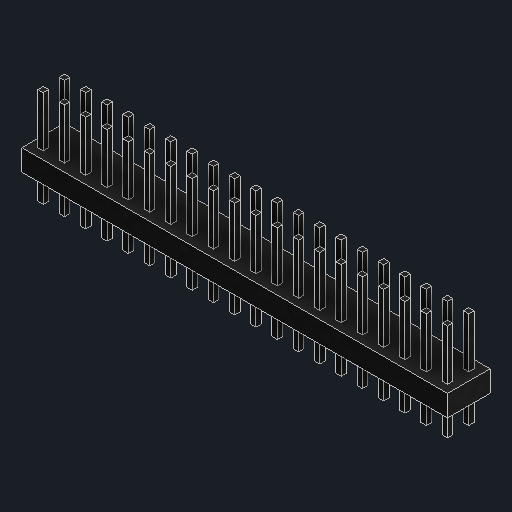
# Autodesk Inventor part: pi_header_2x20
Saved by Autodesk Inventor 2027.1 (Build 311270010, 270A)
## iProperties
Created: 2026-10-29
Part Number: pi_header_2x20
Material: Generic
Document SubType Name: Modeling
Designer: alexg
Density: 1 g/cm^3
Appearance: Black
Author: alexg
Autodesk Inventor part; units mm, degrees
ref_plane "YZ Plane" through (0, 0, 0) normal (1, 0, 0) x (0, 1, 0)
ref_plane "XY Plane" through (0, 0, 0) normal (0, 0, 1) x (1, 0, 0)
sketch "Plastic sketch" plane through (0, 0, 0) normal (0, 1, 0) x (-1, 0, 0)
  line L0 (25.4, -2.54) -> (-25.4, -2.54)
  line L1 (-25.4, -2.54) -> (-25.4, 2.54)
  line L2 (-25.4, 2.54) -> (25.4, 2.54)
  line L3 (25.4, 2.54) -> (25.4, -2.54)
  constraints: 8 end point, 2 parallel, 1 horizontal, 1 perpendicular
extrude "Plastic" add sketch "Plastic sketch" along normal blind 2.54
ref_plane "Work Plane1" through (0, -3, 0) normal (0, 1, 0) x (-1, 0, 0)
sketch "Pins sketch" plane through (0, -3, 0) normal (0, 1, 0) x (-1, 0, 0)
  line L0 (24.45, -1.59) -> (23.81, -1.59)
  line L1 (23.81, -1.59) -> (23.81, -0.95)
  line L2 (23.81, -0.95) -> (24.45, -0.95)
  line L3 (24.45, -0.95) -> (24.45, -1.59)
  line L4 (24.45, 0.95) -> (23.81, 0.95)
  line L5 (23.81, 0.95) -> (23.81, 1.59)
  line L6 (23.81, 1.59) -> (24.45, 1.59)
  line L7 (24.45, 1.59) -> (24.45, 0.95)
  line L8 (21.91, -1.59) -> (21.27, -1.59)
  line L9 (21.27, -1.59) -> (21.27, -0.95)
  line L10 (21.27, -0.95) -> (21.91, -0.95)
  line L11 (21.91, -0.95) -> (21.91, -1.59)
  line L12 (21.91, 0.95) -> (21.27, 0.95)
  line L13 (21.27, 0.95) -> (21.27, 1.59)
  line L14 (21.27, 1.59) -> (21.91, 1.59)
  line L15 (21.91, 1.59) -> (21.91, 0.95)
  line L16 (19.37, -1.59) -> (18.73, -1.59)
  line L17 (18.73, -1.59) -> (18.73, -0.95)
  line L18 (18.73, -0.95) -> (19.37, -0.95)
  line L19 (19.37, -0.95) -> (19.37, -1.59)
  line L20 (19.37, 0.95) -> (18.73, 0.95)
  line L21 (18.73, 0.95) -> (18.73, 1.59)
  line L22 (18.73, 1.59) -> (19.37, 1.59)
  line L23 (19.37, 1.59) -> (19.37, 0.95)
  line L24 (16.83, -1.59) -> (16.19, -1.59)
  line L25 (16.19, -1.59) -> (16.19, -0.95)
  line L26 (16.19, -0.95) -> (16.83, -0.95)
  line L27 (16.83, -0.95) -> (16.83, -1.59)
  line L28 (16.83, 0.95) -> (16.19, 0.95)
  line L29 (16.19, 0.95) -> (16.19, 1.59)
  line L30 (16.19, 1.59) -> (16.83, 1.59)
  line L31 (16.83, 1.59) -> (16.83, 0.95)
  line L32 (14.29, -1.59) -> (13.65, -1.59)
  line L33 (13.65, -1.59) -> (13.65, -0.95)
  line L34 (13.65, -0.95) -> (14.29, -0.95)
  line L35 (14.29, -0.95) -> (14.29, -1.59)
  line L36 (14.29, 0.95) -> (13.65, 0.95)
  line L37 (13.65, 0.95) -> (13.65, 1.59)
  line L38 (13.65, 1.59) -> (14.29, 1.59)
  line L39 (14.29, 1.59) -> (14.29, 0.95)
  line L40 (11.75, -1.59) -> (11.11, -1.59)
  line L41 (11.11, -1.59) -> (11.11, -0.95)
  line L42 (11.11, -0.95) -> (11.75, -0.95)
  line L43 (11.75, -0.95) -> (11.75, -1.59)
  line L44 (11.75, 0.95) -> (11.11, 0.95)
  line L45 (11.11, 0.95) -> (11.11, 1.59)
  line L46 (11.11, 1.59) -> (11.75, 1.59)
  line L47 (11.75, 1.59) -> (11.75, 0.95)
  line L48 (9.21, -1.59) -> (8.57, -1.59)
  line L49 (8.57, -1.59) -> (8.57, -0.95)
  line L50 (8.57, -0.95) -> (9.21, -0.95)
  line L51 (9.21, -0.95) -> (9.21, -1.59)
  line L52 (9.21, 0.95) -> (8.57, 0.95)
  line L53 (8.57, 0.95) -> (8.57, 1.59)
  line L54 (8.57, 1.59) -> (9.21, 1.59)
  line L55 (9.21, 1.59) -> (9.21, 0.95)
  line L56 (6.67, -1.59) -> (6.03, -1.59)
  line L57 (6.03, -1.59) -> (6.03, -0.95)
  line L58 (6.03, -0.95) -> (6.67, -0.95)
  line L59 (6.67, -0.95) -> (6.67, -1.59)
  line L60 (6.67, 0.95) -> (6.03, 0.95)
  line L61 (6.03, 0.95) -> (6.03, 1.59)
  line L62 (6.03, 1.59) -> (6.67, 1.59)
  line L63 (6.67, 1.59) -> (6.67, 0.95)
  line L64 (4.13, -1.59) -> (3.49, -1.59)
  line L65 (3.49, -1.59) -> (3.49, -0.95)
  line L66 (3.49, -0.95) -> (4.13, -0.95)
  line L67 (4.13, -0.95) -> (4.13, -1.59)
  line L68 (4.13, 0.95) -> (3.49, 0.95)
  line L69 (3.49, 0.95) -> (3.49, 1.59)
  line L70 (3.49, 1.59) -> (4.13, 1.59)
  line L71 (4.13, 1.59) -> (4.13, 0.95)
  line L72 (1.59, -1.59) -> (0.95, -1.59)
  line L73 (0.95, -1.59) -> (0.95, -0.95)
  line L74 (0.95, -0.95) -> (1.59, -0.95)
  line L75 (1.59, -0.95) -> (1.59, -1.59)
  line L76 (1.59, 0.95) -> (0.95, 0.95)
  line L77 (0.95, 0.95) -> (0.95, 1.59)
  line L78 (0.95, 1.59) -> (1.59, 1.59)
  line L79 (1.59, 1.59) -> (1.59, 0.95)
  line L80 (-0.95, -1.59) -> (-1.59, -1.59)
  line L81 (-1.59, -1.59) -> (-1.59, -0.95)
  line L82 (-1.59, -0.95) -> (-0.95, -0.95)
  line L83 (-0.95, -0.95) -> (-0.95, -1.59)
  line L84 (-0.95, 0.95) -> (-1.59, 0.95)
  line L85 (-1.59, 0.95) -> (-1.59, 1.59)
  line L86 (-1.59, 1.59) -> (-0.95, 1.59)
  line L87 (-0.95, 1.59) -> (-0.95, 0.95)
  line L88 (-3.49, -1.59) -> (-4.13, -1.59)
  line L89 (-4.13, -1.59) -> (-4.13, -0.95)
  line L90 (-4.13, -0.95) -> (-3.49, -0.95)
  line L91 (-3.49, -0.95) -> (-3.49, -1.59)
  line L92 (-3.49, 0.95) -> (-4.13, 0.95)
  line L93 (-4.13, 0.95) -> (-4.13, 1.59)
  line L94 (-4.13, 1.59) -> (-3.49, 1.59)
  line L95 (-3.49, 1.59) -> (-3.49, 0.95)
  line L96 (-6.03, -1.59) -> (-6.67, -1.59)
  line L97 (-6.67, -1.59) -> (-6.67, -0.95)
  line L98 (-6.67, -0.95) -> (-6.03, -0.95)
  line L99 (-6.03, -0.95) -> (-6.03, -1.59)
  line L100 (-6.03, 0.95) -> (-6.67, 0.95)
  line L101 (-6.67, 0.95) -> (-6.67, 1.59)
  line L102 (-6.67, 1.59) -> (-6.03, 1.59)
  line L103 (-6.03, 1.59) -> (-6.03, 0.95)
  line L104 (-8.57, -1.59) -> (-9.21, -1.59)
  line L105 (-9.21, -1.59) -> (-9.21, -0.95)
  line L106 (-9.21, -0.95) -> (-8.57, -0.95)
  line L107 (-8.57, -0.95) -> (-8.57, -1.59)
  line L108 (-8.57, 0.95) -> (-9.21, 0.95)
  line L109 (-9.21, 0.95) -> (-9.21, 1.59)
  line L110 (-9.21, 1.59) -> (-8.57, 1.59)
  line L111 (-8.57, 1.59) -> (-8.57, 0.95)
  line L112 (-11.11, -1.59) -> (-11.75, -1.59)
  line L113 (-11.75, -1.59) -> (-11.75, -0.95)
  line L114 (-11.75, -0.95) -> (-11.11, -0.95)
  line L115 (-11.11, -0.95) -> (-11.11, -1.59)
  line L116 (-11.11, 0.95) -> (-11.75, 0.95)
  line L117 (-11.75, 0.95) -> (-11.75, 1.59)
  line L118 (-11.75, 1.59) -> (-11.11, 1.59)
  line L119 (-11.11, 1.59) -> (-11.11, 0.95)
  line L120 (-13.65, -1.59) -> (-14.29, -1.59)
  line L121 (-14.29, -1.59) -> (-14.29, -0.95)
  line L122 (-14.29, -0.95) -> (-13.65, -0.95)
  line L123 (-13.65, -0.95) -> (-13.65, -1.59)
  line L124 (-13.65, 0.95) -> (-14.29, 0.95)
  line L125 (-14.29, 0.95) -> (-14.29, 1.59)
  line L126 (-14.29, 1.59) -> (-13.65, 1.59)
  line L127 (-13.65, 1.59) -> (-13.65, 0.95)
  line L128 (-16.19, -1.59) -> (-16.83, -1.59)
  line L129 (-16.83, -1.59) -> (-16.83, -0.95)
  line L130 (-16.83, -0.95) -> (-16.19, -0.95)
  line L131 (-16.19, -0.95) -> (-16.19, -1.59)
  line L132 (-16.19, 0.95) -> (-16.83, 0.95)
  line L133 (-16.83, 0.95) -> (-16.83, 1.59)
  line L134 (-16.83, 1.59) -> (-16.19, 1.59)
  line L135 (-16.19, 1.59) -> (-16.19, 0.95)
  line L136 (-18.73, -1.59) -> (-19.37, -1.59)
  line L137 (-19.37, -1.59) -> (-19.37, -0.95)
  line L138 (-19.37, -0.95) -> (-18.73, -0.95)
  line L139 (-18.73, -0.95) -> (-18.73, -1.59)
  line L140 (-18.73, 0.95) -> (-19.37, 0.95)
  line L141 (-19.37, 0.95) -> (-19.37, 1.59)
  line L142 (-19.37, 1.59) -> (-18.73, 1.59)
  line L143 (-18.73, 1.59) -> (-18.73, 0.95)
  line L144 (-21.27, -1.59) -> (-21.91, -1.59)
  line L145 (-21.91, -1.59) -> (-21.91, -0.95)
  line L146 (-21.91, -0.95) -> (-21.27, -0.95)
  line L147 (-21.27, -0.95) -> (-21.27, -1.59)
  line L148 (-21.27, 0.95) -> (-21.91, 0.95)
  line L149 (-21.91, 0.95) -> (-21.91, 1.59)
  line L150 (-21.91, 1.59) -> (-21.27, 1.59)
  line L151 (-21.27, 1.59) -> (-21.27, 0.95)
  line L152 (-23.81, -1.59) -> (-24.45, -1.59)
  line L153 (-24.45, -1.59) -> (-24.45, -0.95)
  line L154 (-24.45, -0.95) -> (-23.81, -0.95)
  line L155 (-23.81, -0.95) -> (-23.81, -1.59)
  line L156 (-23.81, 0.95) -> (-24.45, 0.95)
  line L157 (-24.45, 0.95) -> (-24.45, 1.59)
  line L158 (-24.45, 1.59) -> (-23.81, 1.59)
  line L159 (-23.81, 1.59) -> (-23.81, 0.95)
  constraints: 320 end point, 80 parallel, 40 horizontal, 40 perpendicular
extrude "Pins" add sketch "Pins sketch" along normal blind 11.54
body "Solid1"
